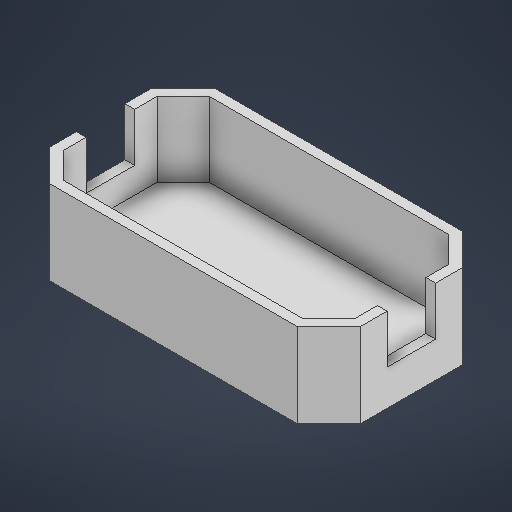
# Autodesk Inventor part: case_v2
Saved by Autodesk Inventor 2026.2 (Build 302298010, 298A)
## iProperties
Created: 2026-08-07
Part Number: case_v2
Material: Generic
Document SubType Name: Modeling
Designer: Kugelblitz
Density: 1 g/cm^3
Appearance: Default
Author: Kugelblitz
Autodesk Inventor part; units mm, degrees
ref_plane "YZ Plane" through (0, 0, 0) normal (1, 0, 0) x (0, 1, 0)
ref_plane "XZ Plane" through (0, 0, 0) normal (0, 1, 0) x (-1, 0, 0)
ref_plane "XY Plane" through (0, 0, 0) normal (0, 0, 1) x (1, 0, 0)
sketch "Sketch1" plane through (0, 0, 0) normal (0, 1, 0) x (-1, 0, 0)
  line L0 (-45, 22.5) -> (45, 22.5)
  line L1 (45, 22.5) -> (45, -22.5)
  line L2 (45, -22.5) -> (-45, -22.5)
  line L3 (-45, -22.5) -> (-45, 22.5)
  line L4 (-45, 22.5) -> (45, -22.5) construction
  line L5 (45, 22.5) -> (-45, -22.5) construction
  line L6 (45, 14.5) -> (37, 22.5)
  line L7 (45, -14.5) -> (37, -22.5)
  line L8 (-37, 22.5) -> (-45, 14.5)
  line L9 (-45, -14.5) -> (-37, -22.5)
  point P0 (0, 0)
  dimension "d0" = 90
  dimension "d1" = 45
  dimension "d4" = 45
  dimension "d5" = 8
  dimension "d6" = 8
  dimension "d7" = 8
  dimension "d8" = 8
  constraints: 20 end point, 8 point on line, 4 perpendicular, 2 midpoint, 2 parallel, 1 horizontal
  measures "d0" distance of L1.end L2.end
  measures "d1" distance of L0.end L1.end
  measures "d4" angle of L1 L6
  measures "d5" distance of L6.start L0.end
  measures "d6" distance of L1.end L7.start
  measures "d7" distance of L8.end L0.start
  measures "d8" distance of L2.end L9.start
extrude "Extrusion1" add sketch "Sketch1" along normal blind 23 contours L0 L6 L1 L7 L2 L9 L3 L8
shell "Shell1" thickness 3 outward yes removed faces 1 at (-12.3333, 23, -7.5)
sketch "Sketch2" plane through (0, 23, 0) normal (0, 1, 0) x (1, 0, 0)
  line L0 (-48, 15.7426) -> (-48, -15.7426) projected
  line L1 (-45, -14.5) -> (-45, 14.5) projected
  line L2 (-48, 7.5) -> (-45, 7.5)
  line L3 (-45, 7.5) -> (-45, -7.5)
  line L4 (-45, -7.5) -> (-48, -7.5)
  line L5 (-48, -7.5) -> (-48, 7.5)
  line L6 (48, -15.7426) -> (48, 15.7426) projected
  line L7 (45, 7.5) -> (48, 7.5)
  line L8 (48, 7.5) -> (48, -7.5)
  line L9 (48, -7.5) -> (45, -7.5)
  line L10 (45, -7.5) -> (45, 7.5)
  line L11 (45, 14.5) -> (45, -14.5) projected
  point P0 (0, 0)
  point P1 (-46.5, -7.5)
  point P2 (-45, 0)
  point P3 (-45, 0)
  point P4 (46.5, -7.5)
  point P5 (46.5, 7.5)
  point P6 (45, 0)
  point P7 (45, 0)
  point P8 (48, 7.5)
  point P9 (-48, -7.5)
  point P10 (-45, 7.5)
  dimension "d10" = 15
  dimension "d11" = 0
  dimension "d12" = 0
  dimension "d13" = 15
  dimension "d14" = 0
  constraints: 16 end point, 7 midpoint, 4 parallel, 3 point on line, 2 horizontal, 2 perpendicular
  measures "d10" distance from line of point (-46.5, -7.5) L2
  measures "d11" distance of point (-45, 0) point (-45, 0)
  measures "d12" distance between parallel lines of L11 L10
  measures "d13" distance of point (46.5, -7.5) point (46.5, 7.5)
  measures "d14" distance of point (45, 0) point (45, 0)
extrude "Extrusion2" cut sketch "Sketch2" against normal blind 15
body "Solid1"
